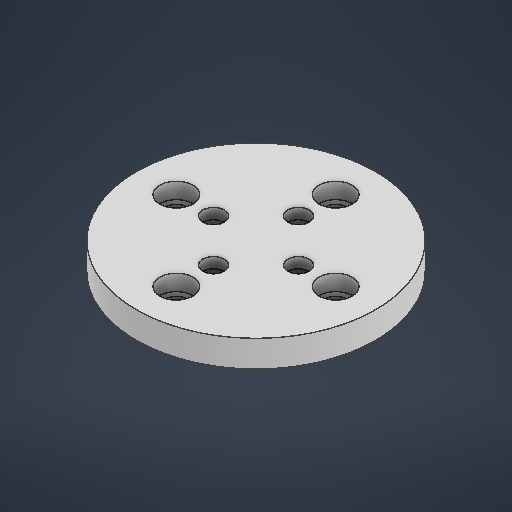
# Autodesk Inventor part: coupler
Saved by Autodesk Inventor 2026.2 (Build 302298010, 298A)
## iProperties
Created: 2026-04-01
Part Number: coupler
Material: 일반
Document SubType Name: Modeling
Designer: work
Density: 1 g/cm^3
Appearance: 기본값
Author: work
Autodesk Inventor part; units mm, degrees
ref_plane "YZ Plane" through (0, 0, 0) normal (1, 0, 0) x (0, 1, 0)
ref_plane "XZ Plane" through (0, 0, 0) normal (0, 1, 0) x (-1, 0, 0)
ref_plane "XY Plane" through (0, 0, 0) normal (0, 0, 1) x (1, 0, 0)
sketch "스케치1" plane through (0, 0, 0) normal (0, 1, 0) x (-1, 0, 0)
  circle A0 centre (0, 0) radius 22.5
  circle A1 centre (0, 0) radius 15
  line L0 (0, 0) -> (15, 0)
  dimension "d1" = 30
  dimension "d0" = 45
  constraints: 2 coincident, 2 end point, 1 centre point, 1 horizontal, 1 horizontal alignment, 2 other
  measures "d0" diameter of A0
extrude "돌출1" add sketch "스케치1" along normal blind 5 contours A0 | A1
sketch "스케치2" plane through (0, 5, 0) normal (0, 1, 0) x (1, 0, 0)
  line L0 (0, 0) -> (-15, 0) construction
  dimension "d4" = 15
  constraints: 2 end point, 1 coincident, 1 horizontal
  measures "d4" distance of L0.start L0.end
hole "구멍1" at (-15, 5, 0) direction (0, -1, 0) diameter 4 end through all counterbore diameter 6.2 counterbore depth 3
pattern_circular "원형 패턴1" count 4 over 360 about axis through (0, -10, 0) along (0, 1, 0) of "구멍1"
sketch "스케치3" plane through (0, 0, 0) normal (0, -1, 0) x (1, 0, 0)
  line L0 (0, 0) -> (0, 8)
  dimension "d15" = 8
  constraints: 2 end point, 1 coincident, 1 vertical
  measures "d15" distance of L0.start L0.end
hole "구멍2" at (0, 0, 8) direction (0, 1, 0) diameter 4 end through all counterbore diameter 6.2 counterbore depth 3
pattern_circular "원형 패턴2" count 4 over 360 about axis through (0, -10, 0) along (0, 1, 0) of "구멍2"
